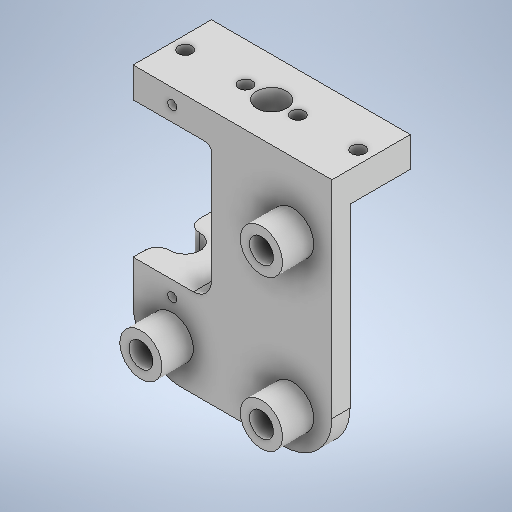
# Autodesk Inventor part: tarttujan runko
Saved by Autodesk Inventor 2025.3 (Build 293356000, 356)
## iProperties
Created: 2025-10-14
Part Number: tarttujan runko
Material: Generic
Document SubType Name: Modeling
Designer: kuuse
Density: 1 g/cm^3
Appearance: Default
Author: kuuse
## iProperties of the stored document tarttujan runko_3DPrint.ipt
Created: 2025-11-05
Part Number: tarttujan runko_3DPrint
Material: Generic
Document SubType Name: Modeling
Designer: kuuse
Density: 1 g/cm^3
Appearance: Default
Author: kuuse
Autodesk Inventor part; units mm, degrees
ref_plane "YZ Plane" through (0, 0, 0) normal (1, 0, 0) x (0, 1, 0)
ref_plane "XZ Plane" through (0, 0, 0) normal (0, 1, 0) x (-1, 0, 0)
ref_plane "XY Plane" through (0, 0, 0) normal (0, 0, 1) x (1, 0, 0)
sketch "Sketch1" plane through (0, 0, 0) normal (0, 0, 1) x (1, 0, 0)
  line L0 (-16.5, -21.15) -> (16.5, -21.15)
  line L1 (16.5, -21.15) -> (16.5, 21.15)
  line L2 (16.5, 21.15) -> (-16.5, 21.15)
  line L3 (-16.5, 21.15) -> (-16.5, -21.15)
  line L4 (-16.5, -21.15) -> (16.5, 21.15) construction
  line L5 (16.5, -21.15) -> (-16.5, 21.15) construction
  line L6 (16.5, 16.15) -> (-16.5, 16.15)
  circle A0 centre (10, 10.35) radius 2
  circle A1 centre (10, -14.65) radius 2
  circle A2 centre (-10, -14.65) radius 2
  line L7 (10, -14.65) -> (10, 10.35) construction
  circle A3 centre (10, 10.35) radius 3.5
  circle A4 centre (10, -14.65) radius 3.5
  circle A5 centre (-10, -14.65) radius 3.5
  line L8 (10, -14.65) -> (-10, -14.65) construction
  line L9 (10, 10.35) -> (-10, 10.35) construction
  line L10 (-10, -14.65) -> (-10, 10.35) construction
  line L11 (-16.5, -6.45) -> (-3.5, -6.45)
  line L12 (-3.5, -6.45) -> (-3.5, -11.45)
  line L13 (-3.5, -11.45) -> (-16.5, -11.45)
  circle A6 centre (-10, -8.95) radius 0.75
  line L14 (-10, 10.35) -> (-10, 18.65) construction
  circle A7 centre (-10, 18.65) radius 0.75
  line L15 (-3.5, -6.45) -> (-3.5, 16.15)
  line L16 (7.9215, 6.75) -> (5.8431, 10.35)
  line L17 (5.8431, 10.35) -> (7.9215, 13.95)
  line L18 (7.9215, 13.95) -> (12.0785, 13.95)
  line L19 (12.0785, 13.95) -> (14.1569, 10.35)
  line L20 (14.1569, 10.35) -> (12.0785, 6.75)
  line L21 (12.0785, 6.75) -> (7.9215, 6.75)
  line L22 (7.9215, -18.25) -> (5.8431, -14.65)
  line L23 (5.8431, -14.65) -> (7.9215, -11.05)
  line L24 (7.9215, -11.05) -> (12.0785, -11.05)
  line L25 (12.0785, -11.05) -> (14.1569, -14.65)
  line L26 (14.1569, -14.65) -> (12.0785, -18.25)
  line L27 (12.0785, -18.25) -> (7.9215, -18.25)
  line L28 (-7.9215, -18.25) -> (-12.0785, -18.25)
  line L29 (-12.0785, -18.25) -> (-14.1569, -14.65)
  line L30 (-14.1569, -14.65) -> (-12.0785, -11.05)
  line L31 (-12.0785, -11.05) -> (-7.9215, -11.05)
  line L32 (-7.9215, -11.05) -> (-5.8431, -14.65)
  line L33 (-5.8431, -14.65) -> (-7.9215, -18.25)
  point P0 (0, 0)
  point P1 (-16.5, 18.8693)
  point P2 (1.6882, 16.15)
  point P3 (8.4638, 15.9)
  point P4 (11.5362, 15.9)
  point P5 (0, 21.15)
  point P6 (-11.4177, -11.45)
  point P7 (-8.5823, -11.45)
  point P8 (10, 13.95)
  point P9 (-6.8823, -12.85)
  dimension "d0" = 5
  dimension "d4" = 5.8
  dimension "d10" = 4
  dimension "d18" = 13
  dimension "d19" = 5
  dimension "d24" = 33
  dimension "d25" = 7
  dimension "d26" = 1.5
  dimension "d27" = 1.5
  dimension "d28" = 27.6
  dimension "d29" = 2.5
  dimension "d30" = 2.5
  dimension "d31" = 20
  dimension "d32" = 10
  dimension "d33" = 25
  dimension "d57" = 6.5
  dimension "d60" = 7.2
  dimension "d61" = 7.2
  dimension "d62" = 7.2
  constraints: 68 end point, 8 centre point, 8 coincident, 8 point on line, 6 horizontal, 6 perpendicular, 5 midpoint, 4 equal radius, 3 vertical, 2 parallel, 39 other
  measures "d0" distance between parallel lines of L2 L6
  measures "d4" distance from line of L6 L9.end
  measures "d10" diameter of A1
  measures "d18" distance between parallel lines of L12 L3
  measures "d19" distance between parallel lines of L11 L13
  measures "d24" distance between parallel lines of L3 L1
  measures "d25" diameter of A5
  measures "d26" diameter of A6
  measures "d27" diameter of A7
  measures "d28" distance of L14.end A6.centre
  measures "d29" distance from line of L11 A6.centre
  measures "d30" distance from line of L6 L14.end
  measures "d31" distance between parallel lines of L7 L10
  measures "d32" horizontal distance of L7.start point (0, 0)
  measures "d33" distance of L7.start L7.end
  measures "d57" distance from line of L0 A2.centre
  measures "d60" distance from line of point (10, 13.95) L21
  measures "d61" distance between parallel lines of L22 L25
  measures "d62" distance from line of L29 point (-6.882, -12.85)
extrude "Extrusion1" add sketch "Sketch1" along normal blind 3 contours L3 L13 L30 L29 L28 L33 L32 L12 L15 L6 L1 L0 | L3 L11 L12 L13 L32 L31 L30 | L6 L3 L2 L1 | L30 L31 L32 L13 A5 | L13 A5 L32 L33 L28 L29 L30 | L13 A5 | A5 L13 | A3 | A4 | L16 L17 L18 L19 L20 L21 | L22 L23 L24 L25 L26 L27
extrude "Extrusion2" add sketch "Sketch1" against normal blind 10 contours L3 L11 L12 L13 L32 L31 L30 | L6 L3 L2 L1 | L30 L31 L32 L13 A5
extrude "Extrusion6" add sketch "Sketch1" along normal blind 5.2 from surface at 3 contours L13 A5 | A5 L13 | A3 | A4
extrude "Extrusion7" cut sketch "Sketch1" along normal blind 1 and the other way blind 40 contours L30 L31 L32 L13 A5 | L13 A5 L32 L33 L28 L29 L30 | L13 A5 | A5 L13 | A0 | A1 | A2 | A3 | A4 | L16 L17 L18 L19 L20 L21 | L22 L23 L24 L25 L26 L27
fillet "Fillet1" radius 8 2 edges at (16.5, -21.15, 1.5) (-16.5, -21.15, 1.5)
sketch "Sketch2" plane through (-16.5, 21.15, 3) normal (0, 1, 0) x (1, 0, 0)
  line L0 (0, 13) -> (0, 0) projected
  line L1 (33, 0) -> (0, 0) projected
  line L2 (33, 0) -> (33, 13) projected
  line L3 (0, 13) -> (33, 13) projected
  line L4 (0, 6.5) -> (33, 6.5) construction
  circle A0 centre (16.5, 6.5) radius 2.5
  circle A1 centre (2.15, 6.5) radius 1.125
  circle A2 centre (30.85, 6.5) radius 1.125
  circle A3 centre (20.85, 6.5) radius 1.125
  circle A4 centre (12.15, 6.5) radius 1.125
  circle A5 centre (2.15, 6.5) radius 2.5
  circle A6 centre (12.15, 6.5) radius 2.5
  line L5 (0, 3) -> (13, 3)
  line L6 (0, 13) -> (0, 0) projected
  line L7 (13, 3) -> (13, 0) projected
  line L8 (13, 3) -> (13, 0) projected
  point P0 (16.5, 3)
  point P1 (14.325, 5.2674)
  point P2 (14.325, 7.7326)
  point P3 (12, 0)
  point P4 (13, 0)
  point P5 (13, 0)
  point P6 (13, 3)
  dimension "d35" = 5
  dimension "d36" = 2.25
  dimension "d37" = 2.25
  dimension "d38" = 14.35
  dimension "d39" = 14.35
  dimension "d40" = 2.25
  dimension "d41" = 2.25
  dimension "d42" = 10
  dimension "d43" = 10
  dimension "d47" = 5
  constraints: 7 centre point, 6 point on line, 4 end point, 3 midpoint, 2 coincident, 1 equal radius, 1 horizontal
  measures "d35" diameter of A0
  measures "d36" diameter of A1
  measures "d37" diameter of A2
  measures "d38" distance of A0.centre A2.centre
  measures "d39" distance of A1.centre A0.centre
  measures "d40" diameter of A3
  measures "d41" diameter of A4
  measures "d42" distance of A2.centre A3.centre
  measures "d43" distance of A1.centre A4.centre
  measures "d47" diameter of A6
extrude "Extrusion3" cut sketch "Sketch2" against normal blind 10 contours A0 A6 | A6 A0 | A1 | A2 | A3 | A4 picked at (17.5264, 6.3029) picked at (14.2255, 6.5)
extrude "Extrusion4" cut sketch "Sketch2" against normal blind 10 from surface at -27.6 contours A5 L0 | L0 A5 | A0 A6 | A1 | A4 picked at (13.6942, 5.427)
fillet "Fillet2" radius 2 4 edges at (-16.5, -8.95, -2.2243) (-16.5, -8.95, -4.7757) (-3.5, -8.95, -1.1489) (-3.5, -8.95, -5.8511)
fillet "Fillet3" radius 3 1 edges at (-3.5, -6.45, 1.5)
fillet "Fillet4" radius 1 1 edges at (-3.5, 16.15, 1.5)
equation "\"d32\" = 0.5 * d31"
body "Solid1"
